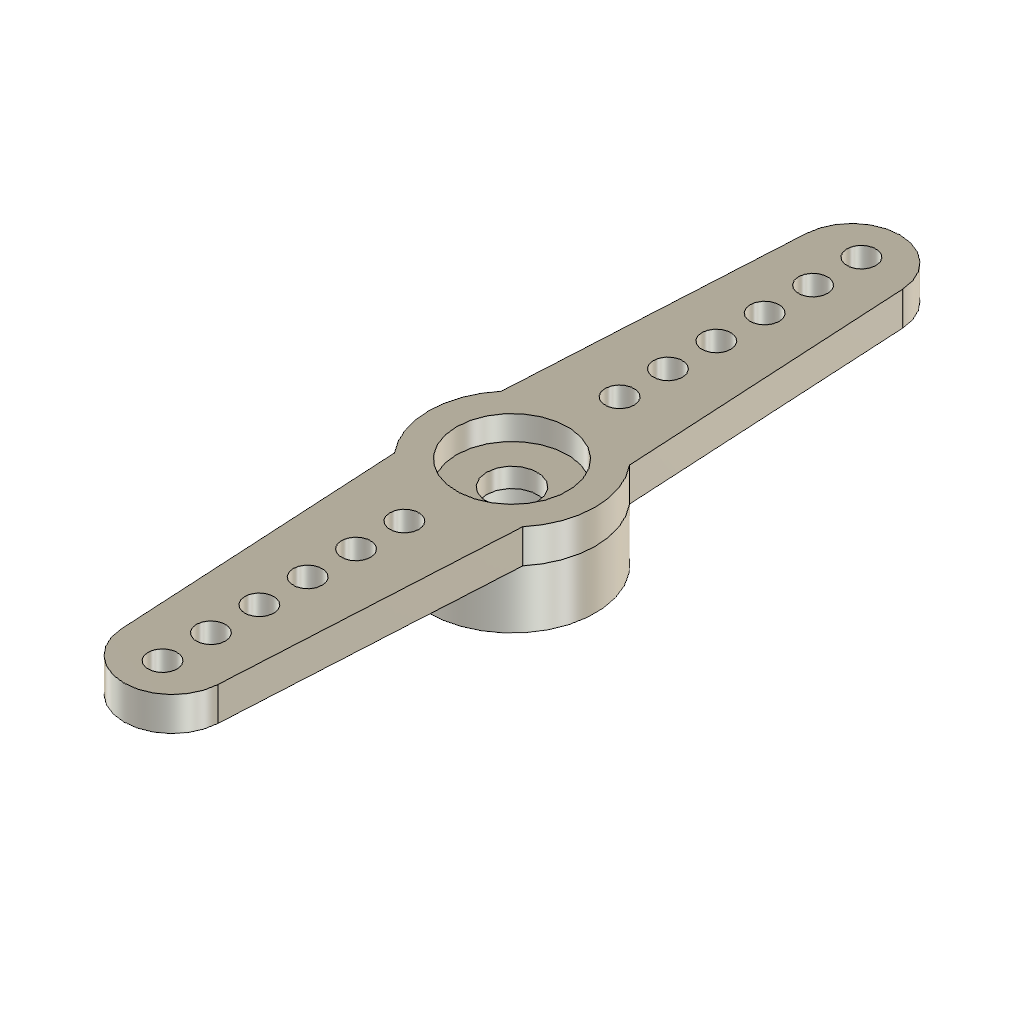
SG90 Horn native (Autodesk Fusion 360 design; units mm, degrees)
part number: 2026-10-14-09-23-30-324
Autodesk Fusion 360 part; units mm, degrees
ref_plane "WorkPlane1" through (0, 0, 6.65) normal (0, 0, 1) x (1, 0, 0)
sketch "Hub" plane through (0, 0, 6.65) normal (0, 0, 1) x (1, 0, 0)
  circle A0 centre (0, 0) radius 3.45
  dimension "d69" = 6.9
  constraint coincident A0.centre origin
  measures "d69" diameter of A0
extrude "Hub (1)" add sketch "Hub" along normal mid plane 2.4
ref_plane "WorkPlane2" through (0, 0, 8.55) normal (0, 0, 1) x (1, 0, 0)
sketch "Arms" plane through (0, 0, 8.55) normal (0, 0, 1) x (1, 0, 0)
  line L0 (-2.65, -2.2091) -> (-1.997, -14.1591)
  arc A0 (-1.997, -14.1591) -> (1.997, -14.1591) centre (0, -14.05) ccw
  line L1 (1.997, -14.1591) -> (2.65, -2.2091)
  arc A1 (2.65, -2.2091) -> (2.65, 2.2091) centre (0, 0) ccw
  line L2 (2.65, 2.2091) -> (1.997, 14.1591)
  arc A2 (1.997, 14.1591) -> (-1.997, 14.1591) centre (0, 14.05) ccw
  line L3 (-1.997, 14.1591) -> (-2.65, 2.2091)
  arc A3 (-2.65, 2.2091) -> (-2.65, -2.2091) centre (0, 0) ccw
  dimension "d70" = 2
  dimension "d71" = 3.45
  dimension "d72" = 14.05
  dimension "d73" = 14.05
  dimension "d74" = 2.65
  dimension "d75" = 1.997
  dimension "d76" = 2.65
  dimension "d77" = 1.997
  constraint tangent L0 A0
  constraint tangent A0 L1
  constraint tangent L2 A2
  constraint tangent A2 L3
  constraint coincident A1.centre A3.centre
  constraint equal A0 A2
  constraint equal A1 A3
  constraint vertical A1.centre A0.centre
  constraint vertical A1.centre A2.centre
  measures "d70" radius of A0
  measures "d71" radius of A1
  measures "d72" vertical distance of A1.centre A0.centre
  measures "d73" vertical distance of A1.centre A2.centre
  measures "d74" horizontal distance of A1.centre L0.start
  measures "d75" horizontal distance of A1.centre A0.end
  measures "d76" horizontal distance of A1.centre A1.end
  measures "d77" horizontal distance of A1.centre A2.end
extrude "Arms (1)" add sketch "Arms" along normal mid plane 1.4
ref_plane "WorkPlane3" through (0, 0, 6.2) normal (0, 0, 1) x (1, 0, 0)
sketch "Spline socket" plane through (0, 0, 6.2) normal (0, 0, 1) x (1, 0, 0)
  circle A0 centre (0, 0) radius 2.45
  dimension "d78" = 4.9
  constraint coincident A0.centre origin
  measures "d78" diameter of A0
extrude "Spline socket (1)" cut sketch "Spline socket" along normal mid plane 2.5
ref_plane "WorkPlane4" through (0, 0, 8.35) normal (0, 0, 1) x (1, 0, 0)
sketch "Screw hole" plane through (0, 0, 8.35) normal (0, 0, 1) x (1, 0, 0)
  circle A0 centre (0, 0) radius 1.05
  dimension "d79" = 2.1
  constraint coincident A0.centre origin
  measures "d79" diameter of A0
extrude "Screw hole (1)" cut sketch "Screw hole" along normal mid plane 2.8
ref_plane "WorkPlane5" through (0, 0, 9) normal (0, 0, 1) x (1, 0, 0)
sketch "Counterbore" plane through (0, 0, 9) normal (0, 0, 1) x (1, 0, 0)
  circle A0 centre (0, 0) radius 2.3
  dimension "d80" = 4.6
  constraint coincident A0.centre origin
  measures "d80" diameter of A0
extrude "Counterbore (1)" cut sketch "Counterbore" along normal mid plane 1.5
ref_plane "WorkPlane6" through (0, 0, 8.55) normal (0, 0, 1) x (1, 0, 0)
sketch "Hole +4.45" plane through (0, 0, 8.55) normal (0, 0, 1) x (1, 0, 0)
  circle A0 centre (0, 4.45) radius 0.6
  dimension "d81" = 1.2
  dimension "d82" = 4.45
  constraint vertical origin A0.centre
  measures "d81" diameter of A0
  measures "d82" vertical distance of origin A0.centre
extrude "Hole +4.45 (1)" cut sketch "Hole +4.45" along normal mid plane 2.4
ref_plane "WorkPlane7" through (0, 0, 8.55) normal (0, 0, 1) x (1, 0, 0)
sketch "Hole -4.45" plane through (0, 0, 8.55) normal (0, 0, 1) x (1, 0, 0)
  circle A0 centre (0, -4.45) radius 0.6
  dimension "d83" = 1.2
  dimension "d84" = 4.45
  constraint vertical origin A0.centre
  measures "d83" diameter of A0
  measures "d84" vertical distance of origin A0.centre
extrude "Hole -4.45 (1)" cut sketch "Hole -4.45" along normal mid plane 2.4
ref_plane "WorkPlane8" through (0, 0, 8.55) normal (0, 0, 1) x (1, 0, 0)
sketch "Hole +6.45" plane through (0, 0, 8.55) normal (0, 0, 1) x (1, 0, 0)
  circle A0 centre (0, 6.45) radius 0.6
  dimension "d85" = 1.2
  dimension "d86" = 6.45
  constraint vertical origin A0.centre
  measures "d85" diameter of A0
  measures "d86" vertical distance of origin A0.centre
extrude "Hole +6.45 (1)" cut sketch "Hole +6.45" along normal mid plane 2.4
ref_plane "WorkPlane9" through (0, 0, 8.55) normal (0, 0, 1) x (1, 0, 0)
sketch "Hole -6.45" plane through (0, 0, 8.55) normal (0, 0, 1) x (1, 0, 0)
  circle A0 centre (0, -6.45) radius 0.6
  dimension "d87" = 1.2
  dimension "d88" = 6.45
  constraint vertical origin A0.centre
  measures "d87" diameter of A0
  measures "d88" vertical distance of origin A0.centre
extrude "Hole -6.45 (1)" cut sketch "Hole -6.45" along normal mid plane 2.4
ref_plane "WorkPlane10" through (0, 0, 8.55) normal (0, 0, 1) x (1, 0, 0)
sketch "Hole +8.45" plane through (0, 0, 8.55) normal (0, 0, 1) x (1, 0, 0)
  circle A0 centre (0, 8.45) radius 0.6
  dimension "d89" = 1.2
  dimension "d90" = 8.45
  constraint vertical origin A0.centre
  measures "d89" diameter of A0
  measures "d90" vertical distance of origin A0.centre
extrude "Hole +8.45 (1)" cut sketch "Hole +8.45" along normal mid plane 2.4
ref_plane "WorkPlane11" through (0, 0, 8.55) normal (0, 0, 1) x (1, 0, 0)
sketch "Hole -8.45" plane through (0, 0, 8.55) normal (0, 0, 1) x (1, 0, 0)
  circle A0 centre (0, -8.45) radius 0.6
  dimension "d91" = 1.2
  dimension "d92" = 8.45
  constraint vertical origin A0.centre
  measures "d91" diameter of A0
  measures "d92" vertical distance of origin A0.centre
extrude "Hole -8.45 (1)" cut sketch "Hole -8.45" along normal mid plane 2.4
ref_plane "WorkPlane12" through (0, 0, 8.55) normal (0, 0, 1) x (1, 0, 0)
sketch "Hole +10.45" plane through (0, 0, 8.55) normal (0, 0, 1) x (1, 0, 0)
  circle A0 centre (0, 10.45) radius 0.6
  dimension "d93" = 1.2
  dimension "d94" = 10.45
  constraint vertical origin A0.centre
  measures "d93" diameter of A0
  measures "d94" vertical distance of origin A0.centre
extrude "Hole +10.45 (1)" cut sketch "Hole +10.45" along normal mid plane 2.4
ref_plane "WorkPlane13" through (0, 0, 8.55) normal (0, 0, 1) x (1, 0, 0)
sketch "Hole -10.45" plane through (0, 0, 8.55) normal (0, 0, 1) x (1, 0, 0)
  circle A0 centre (0, -10.45) radius 0.6
  dimension "d95" = 1.2
  dimension "d96" = 10.45
  constraint vertical origin A0.centre
  measures "d95" diameter of A0
  measures "d96" vertical distance of origin A0.centre
extrude "Hole -10.45 (1)" cut sketch "Hole -10.45" along normal mid plane 2.4
ref_plane "WorkPlane14" through (0, 0, 8.55) normal (0, 0, 1) x (1, 0, 0)
sketch "Hole +12.45" plane through (0, 0, 8.55) normal (0, 0, 1) x (1, 0, 0)
  circle A0 centre (0, 12.45) radius 0.6
  dimension "d97" = 1.2
  dimension "d98" = 12.45
  constraint vertical origin A0.centre
  measures "d97" diameter of A0
  measures "d98" vertical distance of origin A0.centre
extrude "Hole +12.45 (1)" cut sketch "Hole +12.45" along normal mid plane 2.4
ref_plane "WorkPlane15" through (0, 0, 8.55) normal (0, 0, 1) x (1, 0, 0)
sketch "Hole -12.45" plane through (0, 0, 8.55) normal (0, 0, 1) x (1, 0, 0)
  circle A0 centre (0, -12.45) radius 0.6
  dimension "d99" = 1.2
  dimension "d100" = 12.45
  constraint vertical origin A0.centre
  measures "d99" diameter of A0
  measures "d100" vertical distance of origin A0.centre
extrude "Hole -12.45 (1)" cut sketch "Hole -12.45" along normal mid plane 2.4
ref_plane "WorkPlane16" through (0, 0, 8.55) normal (0, 0, 1) x (1, 0, 0)
sketch "Hole +14.45" plane through (0, 0, 8.55) normal (0, 0, 1) x (1, 0, 0)
  circle A0 centre (0, 14.45) radius 0.6
  dimension "d101" = 1.2
  dimension "d102" = 14.45
  constraint vertical origin A0.centre
  measures "d101" diameter of A0
  measures "d102" vertical distance of origin A0.centre
extrude "Hole +14.45 (1)" cut sketch "Hole +14.45" along normal mid plane 2.4
ref_plane "WorkPlane17" through (0, 0, 8.55) normal (0, 0, 1) x (1, 0, 0)
sketch "Hole -14.45" plane through (0, 0, 8.55) normal (0, 0, 1) x (1, 0, 0)
  circle A0 centre (0, -14.45) radius 0.6
  dimension "d103" = 1.2
  dimension "d104" = 14.45
  constraint vertical origin A0.centre
  measures "d103" diameter of A0
  measures "d104" vertical distance of origin A0.centre
extrude "Hole -14.45 (1)" cut sketch "Hole -14.45" along normal mid plane 2.4
named bodies: "SG90 Horn native"
